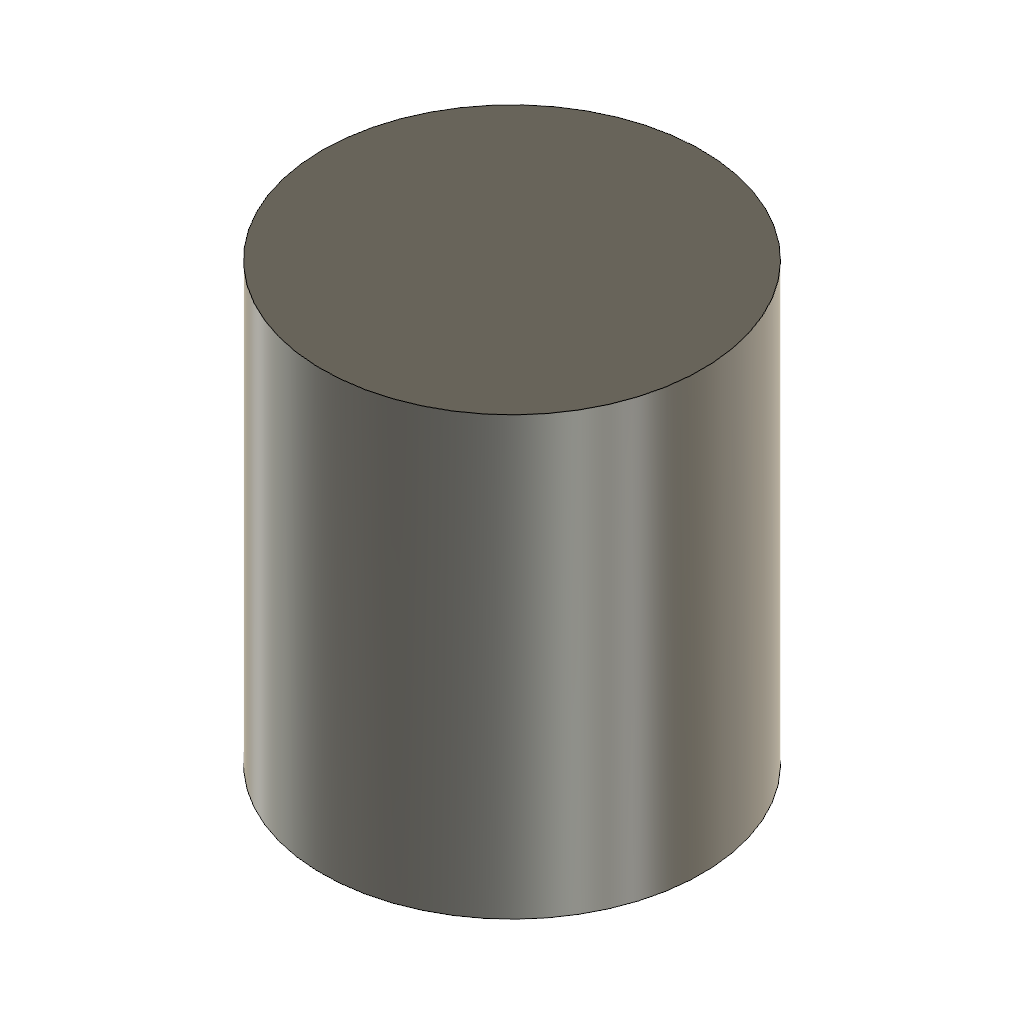
vendor_changed_materials23mm (Autodesk Fusion 360 design; units mm, degrees)
part number: 2026-11-12-02-06-30-590
Autodesk Fusion 360 part; units mm, degrees
sketch "Radius10mm" plane through (0, 0, 0) normal (0, 0, 1) x (1, 0, 0)
  circle A0 centre (0, 0) radius 10
extrude "Kit ControlledExtrusion" add sketch "Radius10mm" along normal blind 23
equation "depthLength = 23 mm" comment "Kit native extrusion control rewrite"
equation "d2 = depthLength"
